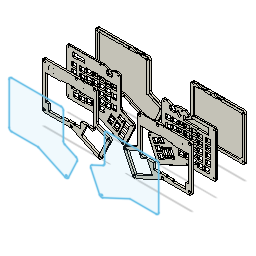
ergodox-replacement-shell-wo-wrist (Autodesk Fusion 360 design; units mm, degrees)
Autodesk Fusion 360 part; units mm, degrees
(part 1 of 3)
sketch "ErgoDOX Case Layer 5 Bottom - Left" plane through (0, 0, 0) normal (0, 0, 1) x (1, 0, 0)
  line L0 (196, 16) -> (196, 16)
  arc A0 (20, -23.440584) -> (27, -30.440584) centre (27, -23.440584) ccw
  line L1 (181.0868, 176.698) -> (181.0868, 97.809302)
  arc A1 (181.0868, 97.809302) -> (185.12868, 91.465051) centre (188.0868, 97.809302) ccw
  arc A2 (221.924958, 66.584374) -> (218.538915, 75.886932) centre (215.580794, 69.542681) ccw
  line L2 (196, 16) -> (196, 16)
  arc A3 (27, 183.698) -> (20, 176.698) centre (27, 176.698) ccw
  arc A4 (181.0868, 176.698) -> (174.0868, 183.698) centre (174.0868, 176.698) ccw
  line L3 (27, 183.698) -> (174.0868, 183.698)
  arc A5 (172.222356, -30.440584) -> (178.56652, -26.398891) centre (172.222356, -23.440584) ccw
  line L4 (185.12868, 91.465051) -> (218.538915, 75.886932)
  line L5 (20, -23.440584) -> (20, 176.698)
  line L6 (221.924958, 66.584374) -> (178.56652, -26.398891)
  line L7 (172.222356, -30.440584) -> (27, -30.440584)
ref_plane "WorkPlane1" through (0, 0, 160) normal (0, 0, 1) x (1, 0, 0)
sketch "ErgoDOX Case Layer 2 Spacer - Left" plane through (0, 0, 160) normal (0, 0, 1) x (1, 0, 0)
  arc A0 (221.924958, 66.584374) -> (218.538915, 75.886932) centre (215.580794, 69.542681) ccw
  line L0 (158.179361, 73.087383) -> (168.641234, 68.208931)
  line L1 (170.666518, 68.946074) -> (177.643945, 83.909215)
  arc A1 (212.634676, 67.592769) -> (212.143248, 68.942958) centre (211.713868, 68.02215) ccw
  circle A2 centre (174.816574, 177.434124) radius 1.5
  circle A3 centre (106.66988, 49.713) radius 1.5
  circle A4 centre (26.263876, 53.119376) radius 1.5
  arc A5 (28.89, 74.119191) -> (29.89, 73.119191) centre (29.89, 74.119191) ccw
  arc A6 (181.0868, 176.698) -> (174.0868, 183.698) centre (174.0868, 176.698) ccw
  line L2 (165.9738, 183.698) -> (174.0868, 183.698)
  arc A7 (158.608741, 75.024191) -> (158.179361, 73.087383) centre (158.608741, 74.008191) ccw
  circle A8 centre (216.558535, 69.898485) radius 1.5
  arc A9 (178.994134, 84.400644) -> (177.643945, 83.909215) centre (178.564754, 83.479835) ccw
  line L3 (152.0941, 178.58498) -> (144.7507, 178.58498)
  line L4 (165.9738, 183.698) -> (152.0941, 178.58498)
  line L5 (172.184141, 150.716191) -> (172.1968, 85.4)
  arc A10 (168.641234, 68.208931) -> (170.666518, 68.946074) centre (169.285305, 69.590144) ccw
  line L6 (142.037, 163.5842) -> (142.037, 177.0842)
  line L7 (178.994134, 84.400644) -> (212.143248, 68.942958)
  arc A11 (181.0868, 97.809302) -> (185.12868, 91.465051) centre (188.0868, 97.809302) ccw
  circle A12 centre (26.263876, 177.434124) radius 1.5
  line L8 (28.89, 74.119191) -> (28.89, 148.827191)
  arc A13 (29.89, 149.827191) -> (28.89, 148.827191) centre (29.89, 148.827191) ccw
  line L9 (212.634676, 67.592769) -> (189.126113, 17.178493)
  line L10 (27, 183.698) -> (130.871, 183.698)
  line L11 (181.0868, 176.698) -> (181.0868, 97.809302)
  circle A14 centre (121.3333, 179.253) radius 1.5
  line L12 (134.084141, 73.500191) -> (134.084141, 58.260191)
  line L13 (95.153498, 57.244191) -> (78.458141, 57.244191)
  line L14 (185.12868, 91.465051) -> (218.538915, 75.886932)
  arc A15 (74.902141, 149.827191) -> (76.426141, 151.351191) centre (74.902141, 151.351191) ccw
  arc A16 (38.326141, 71.595191) -> (36.802141, 73.119191) centre (36.802141, 71.595191) ccw
  arc A17 (75.918141, 54.069191) -> (76.934141, 55.085191) centre (75.918141, 55.085191) ccw
  arc A18 (77.442141, 153.002191) -> (76.426141, 151.986191) centre (77.442141, 151.986191) ccw
  arc A19 (134.288319, 152.494191) -> (135.608141, 151.732191) centre (135.608141, 153.256191) ccw
  arc A20 (151.470453, 72.856121) -> (150.08924, 75.024191) centre (150.08924, 73.500191) ccw
  line L15 (113.002141, 58.831691) -> (97.508141, 58.831691)
  line L16 (145.3078, 178.58498) -> (144.7507, 178.58498)
  line L17 (142.037, 177.0842) -> (154.8078, 177.0842)
  line L18 (20, -23.440584) -> (20, 176.698)
  arc A21 (133.068141, 57.244191) -> (134.084141, 58.260191) centre (133.068141, 58.260191) ccw
  arc A22 (115.145355, 153.954691) -> (116.558141, 153.002191) centre (116.558141, 154.526191) ccw
  arc A23 (187.775924, 16.687064) -> (189.126113, 17.178493) centre (188.205304, 17.607873) ccw
  line L19 (154.8078, 163.5842) -> (142.037, 163.5842)
  arc A24 (114.414927, 57.879191) -> (113.002141, 58.831691) centre (113.002141, 57.307691) ccw
  line L20 (152.0941, 178.58498) -> (151.3078, 178.58498)
  arc A25 (93.952141, 153.002191) -> (95.364927, 153.954691) centre (93.952141, 154.526191) ccw
  line L21 (171.168141, 75.024191) -> (158.608741, 75.024191)
  line L22 (75.918141, 54.069191) -> (39.342141, 54.069191)
  line L23 (135.608141, 151.732191) -> (171.168141, 151.732191)
  arc A26 (96.306784, 154.589691) -> (95.364927, 153.954691) centre (96.306784, 153.573691) ccw
  line L24 (172.222356, -30.440584) -> (27, -30.440584)
  line L25 (96.306784, 154.589691) -> (114.203498, 154.589691)
  arc A27 (20, -23.440584) -> (27, -30.440584) centre (27, -23.440584) ccw
  arc A28 (172.222356, -30.440584) -> (178.56652, -26.398891) centre (172.222356, -23.440584) ccw
  arc A29 (136.870218, 41.545816) -> (137.361647, 40.195627) centre (137.791027, 41.116436) ccw
  arc A30 (97.508141, 58.831691) -> (96.095355, 57.879191) centre (97.508141, 57.307691) ccw
  line L26 (172.184141, 150.716191) -> (172.184141, 76.040191)
  circle A31 centre (26.263876, -24.176684) radius 1.5
  line L27 (154.8078, 177.0842) -> (154.8078, 163.5842)
  arc A32 (171.168141, 75.024191) -> (172.184141, 76.040191) centre (171.168141, 76.040191) ccw
  arc A33 (78.458141, 57.244191) -> (76.934141, 55.720191) centre (78.458141, 55.720191) ccw
  line L28 (76.934141, 55.720191) -> (76.934141, 55.085191)
  line L29 (116.558141, 153.002191) -> (133.408437, 153.002191)
  line L30 (133.068141, 57.244191) -> (115.356784, 57.244191)
  arc A34 (134.288319, 152.494191) -> (133.408437, 153.002191) centre (133.408437, 151.986191) ccw
  arc A35 (115.145355, 153.954691) -> (114.203498, 154.589691) centre (114.203498, 153.573691) ccw
  arc A36 (135.608141, 75.024191) -> (134.084141, 73.500191) centre (135.608141, 73.500191) ccw
  line L31 (38.307845, 160.233267) -> (40.807845, 160.233267)
  line L32 (52.807845, 158.233267) -> (52.807845, 160.233267)
  arc A37 (38.326141, 55.085191) -> (39.342141, 54.069191) centre (39.342141, 55.085191) ccw
  line L33 (136.870218, 41.545816) -> (151.470453, 72.856121)
  line L34 (40.807845, 158.233267) -> (52.807845, 158.233267)
  line L35 (40.807845, 158.233267) -> (40.807845, 160.233267)
  line L36 (77.442141, 153.002191) -> (93.952141, 153.002191)
  line L37 (150.08924, 75.024191) -> (135.608141, 75.024191)
  circle A38 centre (172.941013, -24.568646) radius 1.5
  line L38 (76.426141, 151.351191) -> (76.426141, 151.986191)
  line L39 (36.802141, 73.119191) -> (29.89, 73.119191)
  arc A39 (27, 183.698) -> (20, 176.698) centre (27, 176.698) ccw
  line L40 (144.7507, 178.58498) -> (130.871, 183.698)
  line L41 (38.326141, 55.085191) -> (38.326141, 71.595191)
  line L42 (221.924958, 66.584374) -> (178.56652, -26.398891)
  line L43 (52.807845, 170.435327) -> (52.807845, 172.435327)
  line L44 (40.807845, 170.435327) -> (40.807845, 172.435327)
  arc A40 (114.414927, 57.879191) -> (115.356784, 57.244191) centre (115.356784, 58.260191) ccw
  line L45 (187.775924, 16.687064) -> (137.361647, 40.195627)
  line L46 (38.307845, 170.435327) -> (40.807845, 170.435327)
  line L47 (29.89, 149.827191) -> (74.902141, 149.827191)
  line L48 (40.807845, 172.435327) -> (52.807845, 172.435327)
  arc A41 (172.184141, 150.716191) -> (171.168141, 151.732191) centre (171.168141, 150.716191) ccw
  arc A42 (95.153498, 57.244191) -> (96.095355, 57.879191) centre (95.153498, 58.260191) ccw
  line L49 (52.807845, 170.435327) -> (75, 170.435327)
  line L50 (75, 170.435327) -> (75, 160.233267)
  line L51 (52.807845, 160.233267) -> (75, 160.233267)
  line L52 (38.307845, 160.233267) -> (38.307845, 170.435327)
sketch "ErgoDOX Case Layer 1 Top - Left" plane through (0, 0, 160) normal (0, 0, 1) x (1, 0, 0)
  line L0 (172.222356, -30.440584) -> (27, -30.440584)
  line L1 (20, -23.440584) -> (20, 176.698)
  line L2 (172.184141, 150.716191) -> (172.184141, 76.040191)
  arc A0 (172.184141, 150.716191) -> (171.168141, 151.732191) centre (171.168141, 150.716191) ccw
  arc A1 (172.222356, -30.440584) -> (178.56652, -26.398891) centre (172.222356, -23.440584) ccw
  circle A2 centre (26.263876, -24.176684) radius 1.5
  line L3 (135.608141, 151.732191) -> (171.168141, 151.732191)
  circle A3 centre (172.941013, -24.568646) radius 1.5
  line L4 (221.924958, 66.584374) -> (178.56652, -26.398891)
  line L5 (171.168141, 75.024191) -> (158.608741, 75.024191)
  arc A4 (20, -23.440584) -> (27, -30.440584) centre (27, -23.440584) ccw
  arc A5 (136.870218, 41.545816) -> (137.361647, 40.195627) centre (137.791027, 41.116436) ccw
  line L6 (96.306784, 154.589691) -> (114.203498, 154.589691)
  arc A6 (134.288319, 152.494191) -> (133.408437, 153.002191) centre (133.408437, 151.986191) ccw
  line L7 (178.994134, 84.400644) -> (212.143248, 68.942958)
  line L8 (181.0868, 176.698) -> (181.0868, 97.809302)
  line L9 (133.068141, 57.244191) -> (115.356784, 57.244191)
  arc A7 (114.414927, 57.879191) -> (113.002141, 58.831691) centre (113.002141, 57.307691) ccw
  line L10 (27, 183.698) -> (174.0868, 183.698)
  line L11 (113.002141, 58.831691) -> (97.508141, 58.831691)
  circle A8 centre (216.558535, 69.898485) radius 1.5
  circle A9 centre (106.66988, 49.713) radius 1.5
  line L12 (212.634676, 67.592769) -> (189.126113, 17.178493)
  line L13 (116.558141, 153.002191) -> (133.408437, 153.002191)
  circle A10 centre (121.3333, 179.253) radius 1.5
  line L14 (185.12868, 91.465051) -> (218.538915, 75.886932)
  line L15 (77.442141, 153.002191) -> (93.952141, 153.002191)
  arc A11 (158.608741, 75.024191) -> (158.179361, 73.087383) centre (158.608741, 74.008191) ccw
  arc A12 (178.994134, 84.400644) -> (177.643945, 83.909215) centre (178.564754, 83.479835) ccw
  arc A13 (78.458141, 57.244191) -> (76.934141, 55.720191) centre (78.458141, 55.720191) ccw
  line L16 (136.870218, 41.545816) -> (151.470453, 72.856121)
  arc A14 (115.145355, 153.954691) -> (116.558141, 153.002191) centre (116.558141, 154.526191) ccw
  arc A15 (93.952141, 153.002191) -> (95.364927, 153.954691) centre (93.952141, 154.526191) ccw
  line L17 (172.184141, 150.716191) -> (172.1968, 85.4)
  arc A16 (77.442141, 153.002191) -> (76.426141, 151.986191) centre (77.442141, 151.986191) ccw
  arc A17 (212.634676, 67.592769) -> (212.143248, 68.942958) centre (211.713868, 68.02215) ccw
  arc A18 (27, 183.698) -> (20, 176.698) centre (27, 176.698) ccw
  line L18 (150.08924, 75.024191) -> (135.608141, 75.024191)
  line L19 (76.426141, 151.351191) -> (76.426141, 151.986191)
  circle A19 centre (174.816574, 177.434124) radius 1.5
  arc A20 (151.470453, 72.856121) -> (150.08924, 75.024191) centre (150.08924, 73.500191) ccw
  arc A21 (96.306784, 154.589691) -> (95.364927, 153.954691) centre (96.306784, 153.573691) ccw
  arc A22 (115.145355, 153.954691) -> (114.203498, 154.589691) centre (114.203498, 153.573691) ccw
  arc A23 (133.068141, 57.244191) -> (134.084141, 58.260191) centre (133.068141, 58.260191) ccw
  arc A24 (28.89, 74.119191) -> (29.89, 73.119191) centre (29.89, 74.119191) ccw
  arc A25 (38.326141, 71.595191) -> (36.802141, 73.119191) centre (36.802141, 71.595191) ccw
  line L20 (134.084141, 73.500191) -> (134.084141, 58.260191)
  line L21 (76.934141, 55.720191) -> (76.934141, 55.085191)
  arc A26 (221.924958, 66.584374) -> (218.538915, 75.886932) centre (215.580794, 69.542681) ccw
  line L22 (95.153498, 57.244191) -> (78.458141, 57.244191)
  arc A27 (29.89, 149.827191) -> (28.89, 148.827191) centre (29.89, 148.827191) ccw
  line L23 (187.775924, 16.687064) -> (137.361647, 40.195627)
  arc A28 (135.608141, 75.024191) -> (134.084141, 73.500191) centre (135.608141, 73.500191) ccw
  line L24 (75.918141, 54.069191) -> (39.342141, 54.069191)
  circle A29 centre (26.263876, 177.434124) radius 1.5
  arc A30 (38.326141, 55.085191) -> (39.342141, 54.069191) centre (39.342141, 55.085191) ccw
  line L25 (38.326141, 55.085191) -> (38.326141, 71.595191)
  line L26 (36.802141, 73.119191) -> (29.89, 73.119191)
  arc A31 (168.641234, 68.208931) -> (170.666518, 68.946074) centre (169.285305, 69.590144) ccw
  circle A32 centre (26.263876, 53.119376) radius 1.5
  arc A33 (181.0868, 176.698) -> (174.0868, 183.698) centre (174.0868, 176.698) ccw
  arc A34 (97.508141, 58.831691) -> (96.095355, 57.879191) centre (97.508141, 57.307691) ccw
  arc A35 (95.153498, 57.244191) -> (96.095355, 57.879191) centre (95.153498, 58.260191) ccw
  arc A36 (75.918141, 54.069191) -> (76.934141, 55.085191) centre (75.918141, 55.085191) ccw
  line L27 (28.89, 74.119191) -> (28.89, 148.827191)
  line L28 (158.179361, 73.087383) -> (168.641234, 68.208931)
  line L29 (170.666518, 68.946074) -> (177.643945, 83.909215)
  line L30 (29.89, 149.827191) -> (74.902141, 149.827191)
  arc A37 (74.902141, 149.827191) -> (76.426141, 151.351191) centre (74.902141, 151.351191) ccw
  arc A38 (134.288319, 152.494191) -> (135.608141, 151.732191) centre (135.608141, 153.256191) ccw
  arc A39 (171.168141, 75.024191) -> (172.184141, 76.040191) centre (171.168141, 76.040191) ccw
  arc A40 (114.414927, 57.879191) -> (115.356784, 57.244191) centre (115.356784, 58.260191) ccw
  arc A41 (187.775924, 16.687064) -> (189.126113, 17.178493) centre (188.205304, 17.607873) ccw
  arc A42 (181.0868, 97.809302) -> (185.12868, 91.465051) centre (188.0868, 97.809302) ccw
ref_plane "WorkPlane2" through (0, 0, 85) normal (0, 0, 1) x (1, 0, 0)
sketch "ErgoDOX Case Layer 3 Plate - Left" plane through (0, 0, 85) normal (0, 0, 1) x (1, 0, 0)
  line L0 (131.302846, 60.053437) -> (131.302846, 61.033877)
  line L1 (98.282846, 71.140537) -> (98.282846, 66.131657)
  line L2 (74.152846, 69.867997) -> (74.152846, 70.848437)
  line L3 (74.965646, 57.858877) -> (74.965646, 61.358997)
  line L4 (116.520046, 64.533997) -> (116.520046, 61.033877)
  line L5 (131.302846, 61.033877) -> (132.115646, 61.033877)
  line L6 (74.965646, 61.358997) -> (74.152846, 61.358997)
  line L7 (97.470046, 74.640657) -> (97.470046, 71.140537)
  line L8 (113.065646, 74.640657) -> (112.252846, 74.640657)
  line L9 (98.282846, 66.131657) -> (97.470046, 66.131657)
  line L10 (94.015646, 111.142997) -> (93.202846, 111.142997)
  line L11 (132.115646, 102.633997) -> (131.302846, 102.633997)
  line L12 (112.252846, 113.721097) -> (98.282846, 113.721097)
  line L13 (131.302846, 99.133877) -> (132.115646, 99.133877)
  line L14 (131.302846, 102.633997) -> (131.302846, 107.642877)
  line L15 (116.520046, 107.642877) -> (117.332846, 107.642877)
  line L16 (94.015646, 107.642877) -> (94.015646, 111.142997)
  line L17 (97.470046, 100.731537) -> (98.282846, 100.731537)
  line L18 (98.282846, 99.751097) -> (112.252846, 99.751097)
  line L19 (113.065646, 100.731537) -> (113.065646, 104.231657)
  line L20 (98.282846, 104.231657) -> (97.470046, 104.231657)
  line L21 (93.202846, 99.133877) -> (94.015646, 99.133877)
  line L22 (74.965646, 123.517877) -> (74.965646, 127.017997)
  line L23 (117.332846, 131.173437) -> (117.332846, 130.192997)
  line L24 (131.302846, 130.192997) -> (131.302846, 131.173437)
  line L25 (60.182846, 108.948437) -> (60.182846, 107.967997)
  line L26 (98.282846, 131.790657) -> (97.470046, 131.790657)
  line L27 (113.065646, 128.290537) -> (113.065646, 131.790657)
  line L28 (97.470046, 112.740657) -> (97.470046, 109.240537)
  line L29 (93.202846, 112.123437) -> (79.232846, 112.123437)
  line L30 (78.420046, 107.642877) -> (79.232846, 107.642877)
  line L31 (113.065646, 109.240537) -> (113.065646, 112.740657)
  line L32 (78.420046, 99.133877) -> (79.232846, 99.133877)
  line L33 (93.202846, 102.633997) -> (93.202846, 107.642877)
  line L34 (74.152846, 95.958877) -> (74.965646, 95.958877)
  line L35 (98.282846, 112.740657) -> (97.470046, 112.740657)
  line L36 (98.282846, 100.731537) -> (98.282846, 99.751097)
  line L37 (94.015646, 102.633997) -> (93.202846, 102.633997)
  line L38 (131.302846, 112.123437) -> (117.332846, 112.123437)
  line L39 (116.520046, 111.142997) -> (116.520046, 107.642877)
  line L40 (79.232846, 107.642877) -> (79.232846, 102.633997)
  line L41 (97.470046, 104.231657) -> (97.470046, 100.731537)
  line L42 (112.252846, 112.740657) -> (112.252846, 113.721097)
  line L43 (117.332846, 98.153437) -> (131.302846, 98.153437)
  line L44 (112.252846, 128.290537) -> (113.065646, 128.290537)
  line L45 (131.302846, 140.733997) -> (131.302846, 145.742877)
  line L46 (131.302846, 118.183877) -> (132.115646, 118.183877)
  line L47 (97.470046, 142.331657) -> (97.470046, 138.831537)
  line L48 (131.302846, 136.253437) -> (131.302846, 137.233877)
  line L49 (112.252846, 150.840657) -> (112.252846, 151.821097)
  line L50 (98.282846, 147.340537) -> (98.282846, 142.331657)
  line L51 (113.065646, 138.831537) -> (113.065646, 142.331657)
  line L52 (117.332846, 140.733997) -> (116.520046, 140.733997)
  line L53 (132.115646, 149.242997) -> (131.302846, 149.242997)
  line L54 (132.115646, 130.192997) -> (131.302846, 130.192997)
  line L55 (132.115646, 137.233877) -> (132.115646, 140.733997)
  line L56 (74.152846, 118.508997) -> (74.152846, 123.517877)
  line L57 (113.065646, 123.281657) -> (112.252846, 123.281657)
  line L58 (112.252846, 132.771097) -> (98.282846, 132.771097)
  line L59 (74.965646, 127.017997) -> (74.152846, 127.017997)
  line L60 (98.282846, 132.771097) -> (98.282846, 131.790657)
  line L61 (117.332846, 118.183877) -> (117.332846, 117.203437)
  line L62 (132.115646, 121.683997) -> (131.302846, 121.683997)
  line L63 (131.302846, 126.692877) -> (132.115646, 126.692877)
  line L64 (74.152846, 108.948437) -> (60.182846, 108.948437)
  line L65 (59.370046, 104.467877) -> (60.182846, 104.467877)
  line L66 (60.182846, 115.008877) -> (60.182846, 114.028437)
  line L67 (98.282846, 128.290537) -> (98.282846, 123.281657)
  line L68 (74.152846, 127.017997) -> (74.152846, 127.998437)
  line L69 (74.152846, 123.517877) -> (74.965646, 123.517877)
  line L70 (59.370046, 115.008877) -> (60.182846, 115.008877)
  line L71 (98.282846, 119.781537) -> (98.282846, 118.801097)
  line L72 (59.370046, 107.967997) -> (59.370046, 104.467877)
  line L73 (59.370046, 95.958877) -> (60.182846, 95.958877)
  line L74 (98.282846, 118.801097) -> (112.252846, 118.801097)
  line L75 (98.282846, 137.851097) -> (112.252846, 137.851097)
  line L76 (59.370046, 127.017997) -> (59.370046, 123.517877)
  line L77 (98.282846, 142.331657) -> (97.470046, 142.331657)
  line L78 (117.332846, 149.242997) -> (116.520046, 149.242997)
  line L79 (60.182846, 123.517877) -> (60.182846, 118.508997)
  line L80 (94.015646, 64.533997) -> (93.202846, 64.533997)
  line L81 (117.332846, 145.742877) -> (117.332846, 140.733997)
  line L82 (112.252846, 147.340537) -> (113.065646, 147.340537)
  line L83 (78.420046, 64.533997) -> (78.420046, 61.033877)
  line L84 (78.420046, 69.542877) -> (79.232846, 69.542877)
  line L85 (93.202846, 69.542877) -> (94.015646, 69.542877)
  line L86 (112.252846, 142.331657) -> (112.252846, 147.340537)
  line L87 (60.182846, 127.998437) -> (60.182846, 127.017997)
  line L88 (59.370046, 123.517877) -> (60.182846, 123.517877)
  line L89 (79.232846, 73.042997) -> (78.420046, 73.042997)
  line L90 (93.202846, 73.042997) -> (93.202846, 74.023437)
  line L91 (116.520046, 137.233877) -> (117.332846, 137.233877)
  line L92 (60.182846, 118.508997) -> (59.370046, 118.508997)
  line L93 (59.370046, 118.508997) -> (59.370046, 115.008877)
  line L94 (79.232846, 64.533997) -> (78.420046, 64.533997)
  line L95 (97.470046, 147.340537) -> (98.282846, 147.340537)
  line L96 (112.252846, 80.701097) -> (112.252846, 81.681537)
  line L97 (132.115646, 92.092997) -> (131.302846, 92.092997)
  line L98 (98.282846, 94.671097) -> (98.282846, 93.690657)
  line L99 (98.282846, 81.681537) -> (98.282846, 80.701097)
  line L100 (116.520046, 92.092997) -> (116.520046, 88.592877)
  line L101 (131.302846, 80.083877) -> (132.115646, 80.083877)
  line L102 (135.570046, 78.813877) -> (136.382846, 78.813877)
  line L103 (136.382846, 78.813877) -> (136.382846, 77.833437)
  line L104 (59.370046, 69.867997) -> (59.370046, 66.367877)
  line L105 (98.282846, 93.690657) -> (97.470046, 93.690657)
  line L106 (98.282846, 85.181657) -> (97.470046, 85.181657)
  line L107 (131.302846, 88.592877) -> (132.115646, 88.592877)
  line L108 (117.332846, 73.042997) -> (116.520046, 73.042997)
  line L109 (112.252846, 74.640657) -> (112.252846, 75.621097)
  line L110 (97.470046, 85.181657) -> (97.470046, 81.681537)
  line L111 (117.332846, 79.103437) -> (131.302846, 79.103437)
  line L112 (117.332846, 69.542877) -> (117.332846, 64.533997)
  line L113 (59.370046, 57.858877) -> (60.182846, 57.858877)
  line L114 (112.252846, 93.690657) -> (112.252846, 94.671097)
  line L115 (112.252846, 81.681537) -> (113.065646, 81.681537)
  line L116 (117.332846, 80.083877) -> (117.332846, 79.103437)
  line L117 (136.382846, 87.322877) -> (136.382846, 82.313997)
  line L118 (132.115646, 80.083877) -> (132.115646, 83.583997)
  line L119 (113.065646, 85.181657) -> (112.252846, 85.181657)
  line L120 (98.282846, 80.701097) -> (112.252846, 80.701097)
  line L121 (112.252846, 85.181657) -> (112.252846, 90.190537)
  line L122 (117.332846, 92.092997) -> (116.520046, 92.092997)
  line L123 (135.570046, 87.322877) -> (136.382846, 87.322877)
  line L124 (135.570046, 82.313997) -> (135.570046, 78.813877)
  line L125 (150.352846, 78.813877) -> (151.165646, 78.813877)
  line L126 (151.165646, 78.813877) -> (151.165646, 82.313997)
  line L127 (132.115646, 83.583997) -> (131.302846, 83.583997)
  line L128 (151.165646, 90.822997) -> (150.352846, 90.822997)
  line L129 (74.152846, 70.848437) -> (60.182846, 70.848437)
  line L130 (113.065646, 81.681537) -> (113.065646, 85.181657)
  line L131 (150.352846, 87.322877) -> (151.165646, 87.322877)
  line L132 (98.282846, 90.190537) -> (98.282846, 85.181657)
  line L133 (113.065646, 93.690657) -> (112.252846, 93.690657)
  line L134 (112.252846, 90.190537) -> (113.065646, 90.190537)
  line L135 (164.922286, 125.953737) -> (164.922286, 125.140937)
  line L136 (164.922286, 125.140937) -> (159.913406, 125.140937)
  line L137 (156.413286, 125.953737) -> (156.413286, 125.140937)
  line L138 (170.215646, 139.461457) -> (169.402846, 139.461457)
  line L139 (169.402846, 134.980897) -> (169.402846, 135.961337)
  line L140 (156.413286, 125.140937) -> (155.432846, 125.140937)
  line L141 (155.432846, 111.170937) -> (156.413286, 111.170937)
  line L142 (159.913406, 125.953737) -> (156.413286, 125.953737)
  line L143 (155.432846, 147.970457) -> (154.620046, 147.970457)
  line L144 (169.402846, 135.961337) -> (170.215646, 135.961337)
  line L145 (168.422406, 125.140937) -> (168.422406, 125.953737)
  line L146 (169.402846, 144.470337) -> (170.215646, 144.470337)
  line L147 (155.432846, 125.140937) -> (155.432846, 111.170937)
  line L148 (155.432846, 144.470337) -> (155.432846, 139.461457)
  line L149 (169.402846, 139.461457) -> (169.402846, 144.470337)
  line L150 (154.620046, 144.470337) -> (155.432846, 144.470337)
  line L151 (159.913406, 125.140937) -> (159.913406, 125.953737)
  line L152 (169.402846, 148.950897) -> (155.432846, 148.950897)
  line L153 (168.422406, 125.953737) -> (164.922286, 125.953737)
  line L154 (154.620046, 147.970457) -> (154.620046, 144.470337)
  line L155 (155.432846, 148.950897) -> (155.432846, 147.970457)
  line L156 (154.620046, 135.961337) -> (155.432846, 135.961337)
  line L157 (155.432846, 135.961337) -> (155.432846, 134.980897)
  line L158 (155.432846, 134.980897) -> (169.402846, 134.980897)
  line L159 (170.215646, 135.961337) -> (170.215646, 139.461457)
  line L160 (154.620046, 139.461457) -> (154.620046, 135.961337)
  line L161 (168.422406, 111.170937) -> (169.402846, 111.170937)
  line L162 (155.432846, 139.461457) -> (154.620046, 139.461457)
  line L163 (168.422406, 82.595937) -> (169.402846, 82.595937)
  line L164 (159.913406, 97.378737) -> (156.413286, 97.378737)
  line L165 (159.913406, 82.595937) -> (164.922286, 82.595937)
  line L166 (155.432846, 96.565937) -> (155.432846, 82.595937)
  line L167 (40.320046, 61.358997) -> (40.320046, 57.858877)
  line L168 (55.915646, 69.867997) -> (55.102846, 69.867997)
  line L169 (55.102846, 69.867997) -> (55.102846, 70.848437)
  line L170 (164.922286, 110.358137) -> (168.422406, 110.358137)
  line L171 (136.382846, 128.922997) -> (135.570046, 128.922997)
  line L172 (135.570046, 125.422877) -> (136.382846, 125.422877)
  line L173 (55.102846, 61.358997) -> (55.102846, 66.367877)
  line L174 (55.915646, 66.367877) -> (55.915646, 69.867997)
  line L175 (55.915646, 57.858877) -> (55.915646, 61.358997)
  line L176 (156.413286, 81.783137) -> (159.913406, 81.783137)
  line L177 (55.915646, 61.358997) -> (55.102846, 61.358997)
  line L178 (55.102846, 56.878437) -> (55.102846, 57.858877)
  line L179 (159.913406, 111.170937) -> (164.922286, 111.170937)
  line L180 (155.432846, 82.595937) -> (156.413286, 82.595937)
  line L181 (159.913406, 110.358137) -> (159.913406, 111.170937)
  line L182 (151.165646, 116.913877) -> (151.165646, 120.413997)
  line L183 (156.413286, 111.170937) -> (156.413286, 110.358137)
  line L184 (150.352846, 116.913877) -> (151.165646, 116.913877)
  line L185 (136.382846, 125.422877) -> (136.382846, 120.413997)
  line L186 (169.402846, 82.595937) -> (169.402846, 96.565937)
  line L187 (136.382846, 115.933437) -> (150.352846, 115.933437)
  line L188 (151.165646, 120.413997) -> (150.352846, 120.413997)
  line L189 (41.132846, 61.358997) -> (40.320046, 61.358997)
  line L190 (136.382846, 116.913877) -> (136.382846, 115.933437)
  line L191 (150.352846, 115.933437) -> (150.352846, 116.913877)
  line L192 (156.413286, 82.595937) -> (156.413286, 81.783137)
  line L193 (150.352846, 120.413997) -> (150.352846, 125.422877)
  line L194 (156.413286, 110.358137) -> (159.913406, 110.358137)
  line L195 (41.132846, 69.867997) -> (40.320046, 69.867997)
  line L196 (41.132846, 57.858877) -> (41.132846, 56.878437)
  line L197 (55.102846, 57.858877) -> (55.915646, 57.858877)
  line L198 (41.132846, 70.848437) -> (41.132846, 69.867997)
  line L199 (164.922286, 111.170937) -> (164.922286, 110.358137)
  line L200 (150.352846, 129.903437) -> (136.382846, 129.903437)
  line L201 (41.132846, 56.878437) -> (55.102846, 56.878437)
  line L202 (40.320046, 69.867997) -> (40.320046, 66.367877)
  line L203 (168.422406, 81.783137) -> (168.422406, 82.595937)
  line L204 (164.922286, 97.378737) -> (164.922286, 96.565937)
  line L205 (168.422406, 97.378737) -> (164.922286, 97.378737)
  line L206 (159.913406, 96.565937) -> (159.913406, 97.378737)
  line L207 (40.320046, 66.367877) -> (41.132846, 66.367877)
  line L208 (164.922286, 82.595937) -> (164.922286, 81.783137)
  line L209 (156.413286, 97.378737) -> (156.413286, 96.565937)
  line L210 (136.382846, 129.903437) -> (136.382846, 128.922997)
  line L211 (135.570046, 128.922997) -> (135.570046, 125.422877)
  line L212 (164.922286, 96.565937) -> (159.913406, 96.565937)
  line L213 (168.422406, 110.358137) -> (168.422406, 111.170937)
  line L214 (41.132846, 66.367877) -> (41.132846, 61.358997)
  line L215 (40.320046, 57.858877) -> (41.132846, 57.858877)
  line L216 (169.402846, 96.565937) -> (168.422406, 96.565937)
  line L217 (159.913406, 81.783137) -> (159.913406, 82.595937)
  line L218 (168.422406, 96.565937) -> (168.422406, 97.378737)
  line L219 (55.102846, 70.848437) -> (41.132846, 70.848437)
  line L220 (55.102846, 66.367877) -> (55.915646, 66.367877)
  line L221 (136.382846, 120.413997) -> (135.570046, 120.413997)
  line L222 (135.570046, 120.413997) -> (135.570046, 116.913877)
  line L223 (135.570046, 116.913877) -> (136.382846, 116.913877)
  line L224 (156.413286, 96.565937) -> (155.432846, 96.565937)
  line L225 (194.099266, 69.362537) -> (194.835866, 69.019637)
  line L226 (164.922286, 81.783137) -> (168.422406, 81.783137)
  line L227 (186.050006, 52.098157) -> (186.786606, 51.755257)
  line L228 (195.851866, 38.138317) -> (196.588466, 37.795417)
  line L229 (201.343346, 49.911217) -> (188.681446, 55.816717)
  line L230 (176.618986, 29.949357) -> (175.882386, 30.292257)
  line L231 (190.505166, 61.651097) -> (191.241766, 61.308197)
  line L232 (191.241766, 61.308197) -> (190.825206, 60.419197)
  line L233 (196.316686, 72.192097) -> (195.580086, 72.534997)
  line L234 (195.580086, 72.534997) -> (194.099266, 69.362537)
  line L235 (194.835866, 69.019637) -> (192.720046, 64.480657)
  line L236 (190.825206, 60.419197) -> (203.487106, 54.513697)
  line L237 (203.487106, 54.513697) -> (203.901126, 55.402697)
  line L238 (191.983446, 64.823557) -> (190.505166, 61.651097)
  line L239 (208.976046, 66.286597) -> (209.392606, 67.175597)
  line L240 (199.448506, 45.849757) -> (200.185106, 45.506857)
  line L241 (151.165646, 128.922997) -> (150.352846, 128.922997)
  line L242 (203.901126, 55.402697) -> (204.637726, 55.059797)
  line L243 (206.118546, 58.232257) -> (205.381946, 58.575157)
  line L244 (151.165646, 125.422877) -> (151.165646, 128.922997)
  line L245 (150.352846, 125.422877) -> (151.165646, 125.422877)
  line L246 (201.663386, 48.679317) -> (200.926786, 49.022217)
  line L247 (192.720046, 64.480657) -> (191.983446, 64.823557)
  line L248 (208.234366, 62.771237) -> (209.712646, 65.943697)
  line L249 (204.637726, 55.059797) -> (206.118546, 58.232257)
  line L250 (174.724146, 25.887897) -> (187.386046, 19.982397)
  line L251 (209.712646, 65.943697) -> (208.976046, 66.286597)
  line L252 (200.926786, 49.022217) -> (201.343346, 49.911217)
  line L253 (191.396706, 28.582837) -> (192.133306, 28.239937)
  line L254 (183.934186, 47.559177) -> (182.455906, 44.386717)
  line L255 (207.497766, 63.114137) -> (208.234366, 62.771237)
  line L256 (195.437846, 37.249317) -> (195.851866, 38.138317)
  line L257 (178.734806, 34.488337) -> (176.618986, 29.949357)
  line L258 (190.017486, 23.700957) -> (189.280886, 24.043857)
  line L259 (198.069286, 40.967877) -> (197.332686, 41.310777)
  line L260 (205.381946, 58.575157) -> (207.497766, 63.114137)
  line L261 (193.291546, 32.644297) -> (180.629646, 38.549797)
  line L262 (182.455906, 44.386717) -> (183.192506, 44.043817)
  line L263 (187.530826, 55.270617) -> (186.050006, 52.098157)
  line L264 (184.670786, 47.216277) -> (183.934186, 47.559177)
  line L265 (187.800066, 20.871397) -> (188.536666, 20.528497)
  line L266 (183.192506, 44.043817) -> (182.775946, 43.154817)
  line L267 (180.629646, 38.549797) -> (180.215626, 37.660797)
  line L268 (192.133306, 28.239937) -> (193.611586, 31.412397)
  line L269 (180.215626, 37.660797) -> (179.479026, 38.003697)
  line L270 (200.185106, 45.506857) -> (201.663386, 48.679317)
  line L271 (188.681446, 55.816717) -> (188.267426, 54.927717)
  line L272 (197.332686, 41.310777) -> (199.448506, 45.849757)
  line L273 (189.280886, 24.043857) -> (191.396706, 28.582837)
  line L274 (182.775946, 43.154817) -> (195.437846, 37.249317)
  line L275 (196.588466, 37.795417) -> (198.069286, 40.967877)
  line L276 (179.479026, 38.003697) -> (177.998206, 34.831237)
  line L277 (193.611586, 31.412397) -> (192.874986, 31.755297)
  line L278 (150.352846, 128.922997) -> (150.352846, 129.903437)
  line L279 (177.998206, 34.831237) -> (178.734806, 34.488337)
  line L280 (188.536666, 20.528497) -> (190.017486, 23.700957)
  line L281 (192.874986, 31.755297) -> (193.291546, 32.644297)
  line L282 (209.392606, 67.175597) -> (196.730706, 73.081097)
  line L283 (188.267426, 54.927717) -> (187.530826, 55.270617)
  line L284 (187.386046, 19.982397) -> (187.800066, 20.871397)
  line L285 (186.786606, 51.755257) -> (184.670786, 47.216277)
  line L286 (174.404106, 27.119797) -> (175.140706, 26.776897)
  line L287 (175.882386, 30.292257) -> (174.404106, 27.119797)
  line L288 (93.202846, 137.233877) -> (94.015646, 137.233877)
  line L289 (196.730706, 73.081097) -> (196.316686, 72.192097)
  line L290 (60.182846, 133.075897) -> (74.152846, 133.075897)
  line L291 (179.052306, 80.241357) -> (178.315706, 80.584257)
  line L292 (112.252846, 151.821097) -> (98.282846, 151.821097)
  line L293 (176.834886, 77.411797) -> (177.571486, 77.068897)
  line L294 (60.182846, 146.065457) -> (59.370046, 146.065457)
  line L295 (94.015646, 145.742877) -> (94.015646, 149.242997)
  line L296 (192.128226, 75.224857) -> (179.466326, 81.130357)
  line L297 (93.202846, 145.742877) -> (94.015646, 145.742877)
  line L298 (74.152846, 134.056337) -> (74.965646, 134.056337)
  line L299 (186.636746, 63.451957) -> (187.373346, 63.109057)
  line L300 (187.373346, 63.109057) -> (188.854166, 66.281517)
  line L301 (173.240786, 69.700357) -> (173.977386, 69.357457)
  line L302 (93.202846, 150.223437) -> (79.232846, 150.223437)
  line L303 (98.282846, 150.840657) -> (97.470046, 150.840657)
  line L304 (74.965646, 137.556457) -> (74.152846, 137.556457)
  line L305 (79.232846, 149.242997) -> (78.420046, 149.242997)
  line L306 (60.182846, 147.045897) -> (60.182846, 146.065457)
  line L307 (60.182846, 137.556457) -> (59.370046, 137.556457)
  line L308 (74.152846, 133.075897) -> (74.152846, 134.056337)
  line L309 (175.140706, 26.776897) -> (174.724146, 25.887897)
  line L310 (97.470046, 150.840657) -> (97.470046, 147.340537)
  line L311 (178.315706, 80.584257) -> (176.834886, 77.411797)
  line L312 (192.448266, 73.992957) -> (191.711666, 74.335857)
  line L313 (79.232846, 137.233877) -> (79.232846, 136.253437)
  line L314 (93.202846, 140.733997) -> (93.202846, 145.742877)
  line L315 (179.466326, 81.130357) -> (179.052306, 80.241357)
  line L316 (78.420046, 145.742877) -> (79.232846, 145.742877)
  line L317 (78.420046, 149.242997) -> (78.420046, 145.742877)
  line L318 (175.455666, 72.529917) -> (174.719066, 72.872817)
  line L319 (78.420046, 137.233877) -> (79.232846, 137.233877)
  line L320 (174.719066, 72.872817) -> (173.240786, 69.700357)
  line L321 (188.117566, 66.624417) -> (190.233386, 71.163397)
  line L322 (173.977386, 69.357457) -> (173.560826, 68.468457)
  line L323 (190.233386, 71.163397) -> (190.969986, 70.820497)
  line L324 (94.015646, 137.233877) -> (94.015646, 140.733997)
  line L325 (74.965646, 142.565337) -> (74.965646, 146.065457)
  line L326 (188.854166, 66.281517) -> (188.117566, 66.624417)
  line L327 (74.152846, 147.045897) -> (60.182846, 147.045897)
  line L328 (60.182846, 134.056337) -> (60.182846, 133.075897)
  line L329 (79.232846, 145.742877) -> (79.232846, 140.733997)
  line L330 (59.370046, 146.065457) -> (59.370046, 142.565337)
  line L331 (79.232846, 150.223437) -> (79.232846, 149.242997)
  line L332 (59.370046, 142.565337) -> (60.182846, 142.565337)
  line L333 (191.711666, 74.335857) -> (192.128226, 75.224857)
  line L334 (93.202846, 136.253437) -> (93.202846, 137.233877)
  line L335 (79.232846, 136.253437) -> (93.202846, 136.253437)
  line L336 (173.560826, 68.468457) -> (186.222726, 62.562957)
  line L337 (74.152846, 146.065457) -> (74.152846, 147.045897)
  line L338 (60.182846, 142.565337) -> (60.182846, 137.556457)
  line L339 (74.965646, 134.056337) -> (74.965646, 137.556457)
  line L340 (74.965646, 146.065457) -> (74.152846, 146.065457)
  line L341 (94.015646, 140.733997) -> (93.202846, 140.733997)
  line L342 (74.152846, 142.565337) -> (74.965646, 142.565337)
  line L343 (98.282846, 151.821097) -> (98.282846, 150.840657)
  line L344 (177.571486, 77.068897) -> (175.455666, 72.529917)
  line L345 (190.969986, 70.820497) -> (192.448266, 73.992957)
  line L346 (131.302846, 145.742877) -> (132.115646, 145.742877)
  line L347 (74.152846, 137.556457) -> (74.152846, 142.565337)
  line L348 (117.332846, 150.223437) -> (117.332846, 149.242997)
  line L349 (131.302846, 137.233877) -> (132.115646, 137.233877)
  line L350 (94.015646, 149.242997) -> (93.202846, 149.242997)
  line L351 (93.202846, 149.242997) -> (93.202846, 150.223437)
  line L352 (98.282846, 138.831537) -> (98.282846, 137.851097)
  line L353 (59.370046, 137.556457) -> (59.370046, 134.056337)
  line L354 (59.370046, 134.056337) -> (60.182846, 134.056337)
  line L355 (113.065646, 150.840657) -> (112.252846, 150.840657)
  line L356 (78.420046, 140.733997) -> (78.420046, 137.233877)
  line L357 (79.232846, 140.733997) -> (78.420046, 140.733997)
  line L358 (186.222726, 62.562957) -> (186.636746, 63.451957)
  line L359 (79.232846, 61.033877) -> (79.232846, 60.053437)
  line L360 (78.420046, 73.042997) -> (78.420046, 69.542877)
  line L361 (117.332846, 136.253437) -> (131.302846, 136.253437)
  line L362 (97.470046, 138.831537) -> (98.282846, 138.831537)
  line L363 (79.232846, 69.542877) -> (79.232846, 64.533997)
  line L364 (112.252846, 138.831537) -> (113.065646, 138.831537)
  line L365 (113.065646, 147.340537) -> (113.065646, 150.840657)
  line L366 (132.115646, 145.742877) -> (132.115646, 149.242997)
  line L367 (93.202846, 74.023437) -> (79.232846, 74.023437)
  line L368 (94.015646, 61.033877) -> (94.015646, 64.533997)
  line L369 (79.232846, 60.053437) -> (93.202846, 60.053437)
  line L370 (94.015646, 69.542877) -> (94.015646, 73.042997)
  line L371 (113.065646, 142.331657) -> (112.252846, 142.331657)
  line L372 (132.115646, 140.733997) -> (131.302846, 140.733997)
  line L373 (93.202846, 60.053437) -> (93.202846, 61.033877)
  line L374 (116.520046, 149.242997) -> (116.520046, 145.742877)
  line L375 (94.015646, 73.042997) -> (93.202846, 73.042997)
  line L376 (93.202846, 64.533997) -> (93.202846, 69.542877)
  line L377 (116.520046, 145.742877) -> (117.332846, 145.742877)
  line L378 (131.302846, 149.242997) -> (131.302846, 150.223437)
  line L379 (131.302846, 150.223437) -> (117.332846, 150.223437)
  line L380 (117.332846, 137.233877) -> (117.332846, 136.253437)
  line L381 (116.520046, 140.733997) -> (116.520046, 137.233877)
  line L382 (78.420046, 61.033877) -> (79.232846, 61.033877)
  line L383 (93.202846, 61.033877) -> (94.015646, 61.033877)
  line L384 (112.252846, 137.851097) -> (112.252846, 138.831537)
  line L385 (74.152846, 127.998437) -> (60.182846, 127.998437)
  line L386 (60.182846, 127.017997) -> (59.370046, 127.017997)
  line L387 (79.232846, 74.023437) -> (79.232846, 73.042997)
  line L388 (170.215646, 147.970457) -> (169.402846, 147.970457)
  line L389 (170.215646, 144.470337) -> (170.215646, 147.970457)
  line L390 (169.402846, 111.170937) -> (169.402846, 125.140937)
  line L391 (169.402846, 125.140937) -> (168.422406, 125.140937)
  line L392 (169.402846, 147.970457) -> (169.402846, 148.950897)
  line L393 (113.065646, 112.740657) -> (112.252846, 112.740657)
  line L394 (116.520046, 102.633997) -> (116.520046, 99.133877)
  line L395 (132.115646, 99.133877) -> (132.115646, 102.633997)
  line L396 (74.152846, 99.458997) -> (74.152846, 104.467877)
  line L397 (74.152846, 107.967997) -> (74.152846, 108.948437)
  line L398 (79.232846, 102.633997) -> (78.420046, 102.633997)
  line L399 (79.232846, 98.153437) -> (93.202846, 98.153437)
  line L400 (93.202846, 111.142997) -> (93.202846, 112.123437)
  line L401 (117.332846, 112.123437) -> (117.332846, 111.142997)
  line L402 (78.420046, 111.142997) -> (78.420046, 107.642877)
  line L403 (78.420046, 102.633997) -> (78.420046, 99.133877)
  line L404 (112.252846, 104.231657) -> (112.252846, 109.240537)
  line L405 (98.282846, 113.721097) -> (98.282846, 112.740657)
  line L406 (112.252846, 99.751097) -> (112.252846, 100.731537)
  line L407 (74.152846, 104.467877) -> (74.965646, 104.467877)
  line L408 (93.202846, 107.642877) -> (94.015646, 107.642877)
  line L409 (79.232846, 99.133877) -> (79.232846, 98.153437)
  line L410 (74.965646, 107.967997) -> (74.152846, 107.967997)
  line L411 (79.232846, 111.142997) -> (78.420046, 111.142997)
  line L412 (97.470046, 109.240537) -> (98.282846, 109.240537)
  line L413 (117.332846, 111.142997) -> (116.520046, 111.142997)
  line L414 (74.965646, 104.467877) -> (74.965646, 107.967997)
  line L415 (74.965646, 99.458997) -> (74.152846, 99.458997)
  line L416 (93.202846, 98.153437) -> (93.202846, 99.133877)
  line L417 (74.965646, 95.958877) -> (74.965646, 99.458997)
  line L418 (113.065646, 104.231657) -> (112.252846, 104.231657)
  line L419 (116.520046, 99.133877) -> (117.332846, 99.133877)
  line L420 (117.332846, 99.133877) -> (117.332846, 98.153437)
  line L421 (117.332846, 107.642877) -> (117.332846, 102.633997)
  line L422 (112.252846, 109.240537) -> (113.065646, 109.240537)
  line L423 (117.332846, 102.633997) -> (116.520046, 102.633997)
  line L424 (98.282846, 109.240537) -> (98.282846, 104.231657)
  line L425 (79.232846, 112.123437) -> (79.232846, 111.142997)
  line L426 (94.015646, 99.133877) -> (94.015646, 102.633997)
  line L427 (131.302846, 98.153437) -> (131.302846, 99.133877)
  line L428 (78.420046, 92.092997) -> (78.420046, 88.592877)
  line L429 (93.202846, 88.592877) -> (94.015646, 88.592877)
  line L430 (79.232846, 93.073437) -> (79.232846, 92.092997)
  line L431 (93.202846, 93.073437) -> (79.232846, 93.073437)
  line L432 (93.202846, 79.103437) -> (93.202846, 80.083877)
  line L433 (132.115646, 111.142997) -> (131.302846, 111.142997)
  line L434 (60.182846, 89.898437) -> (60.182846, 88.917997)
  line L435 (74.965646, 76.908877) -> (74.965646, 80.408997)
  line L436 (78.420046, 80.083877) -> (79.232846, 80.083877)
  line L437 (136.382846, 101.363997) -> (135.570046, 101.363997)
  line L438 (59.370046, 76.908877) -> (60.182846, 76.908877)
  line L439 (150.352846, 96.883437) -> (150.352846, 97.863877)
  line L440 (136.382846, 97.863877) -> (136.382846, 96.883437)
  line L441 (74.152846, 76.908877) -> (74.965646, 76.908877)
  line L442 (150.352846, 109.872997) -> (150.352846, 110.853437)
  line L443 (150.352846, 101.363997) -> (150.352846, 106.372877)
  line L444 (135.570046, 106.372877) -> (136.382846, 106.372877)
  line L445 (74.152846, 85.417877) -> (74.965646, 85.417877)
  line L446 (74.152846, 89.898437) -> (60.182846, 89.898437)
  line L447 (132.115646, 107.642877) -> (132.115646, 111.142997)
  line L448 (136.382846, 109.872997) -> (135.570046, 109.872997)
  line L449 (79.232846, 79.103437) -> (93.202846, 79.103437)
  line L450 (151.165646, 109.872997) -> (150.352846, 109.872997)
  line L451 (79.232846, 83.583997) -> (78.420046, 83.583997)
  line L452 (131.302846, 111.142997) -> (131.302846, 112.123437)
  line L453 (150.352846, 110.853437) -> (136.382846, 110.853437)
  line L454 (151.165646, 101.363997) -> (150.352846, 101.363997)
  line L455 (135.570046, 90.822997) -> (135.570046, 87.322877)
  line L456 (97.470046, 90.190537) -> (98.282846, 90.190537)
  line L457 (151.165646, 87.322877) -> (151.165646, 90.822997)
  line L458 (112.252846, 94.671097) -> (98.282846, 94.671097)
  line L459 (131.302846, 92.092997) -> (131.302846, 93.073437)
  line L460 (97.470046, 93.690657) -> (97.470046, 90.190537)
  line L461 (117.332846, 93.073437) -> (117.332846, 92.092997)
  line L462 (136.382846, 90.822997) -> (135.570046, 90.822997)
  line L463 (116.520046, 83.583997) -> (116.520046, 80.083877)
  line L464 (74.152846, 80.408997) -> (74.152846, 85.417877)
  line L465 (74.152846, 75.928437) -> (74.152846, 76.908877)
  line L466 (150.352846, 97.863877) -> (151.165646, 97.863877)
  line L467 (79.232846, 92.092997) -> (78.420046, 92.092997)
  line L468 (94.015646, 80.083877) -> (94.015646, 83.583997)
  line L469 (151.165646, 106.372877) -> (151.165646, 109.872997)
  line L470 (93.202846, 83.583997) -> (93.202846, 88.592877)
  line L471 (94.015646, 92.092997) -> (93.202846, 92.092997)
  line L472 (112.252846, 100.731537) -> (113.065646, 100.731537)
  line L473 (60.182846, 88.917997) -> (59.370046, 88.917997)
  line L474 (78.420046, 88.592877) -> (79.232846, 88.592877)
  line L475 (78.420046, 83.583997) -> (78.420046, 80.083877)
  line L476 (74.965646, 85.417877) -> (74.965646, 88.917997)
  line L477 (74.965646, 80.408997) -> (74.152846, 80.408997)
  line L478 (93.202846, 92.092997) -> (93.202846, 93.073437)
  line L479 (79.232846, 80.083877) -> (79.232846, 79.103437)
  line L480 (60.182846, 76.908877) -> (60.182846, 75.928437)
  line L481 (74.965646, 88.917997) -> (74.152846, 88.917997)
  line L482 (94.015646, 88.592877) -> (94.015646, 92.092997)
  line L483 (74.152846, 88.917997) -> (74.152846, 89.898437)
  line L484 (93.202846, 80.083877) -> (94.015646, 80.083877)
  line L485 (136.382846, 96.883437) -> (150.352846, 96.883437)
  line L486 (59.370046, 85.417877) -> (60.182846, 85.417877)
  line L487 (79.232846, 88.592877) -> (79.232846, 83.583997)
  line L488 (151.165646, 97.863877) -> (151.165646, 101.363997)
  line L489 (136.382846, 110.853437) -> (136.382846, 109.872997)
  line L490 (131.302846, 107.642877) -> (132.115646, 107.642877)
  line L491 (150.352846, 106.372877) -> (151.165646, 106.372877)
  line L492 (60.182846, 80.408997) -> (59.370046, 80.408997)
  line L493 (135.570046, 101.363997) -> (135.570046, 97.863877)
  line L494 (59.370046, 88.917997) -> (59.370046, 85.417877)
  line L495 (136.382846, 106.372877) -> (136.382846, 101.363997)
  line L496 (59.370046, 80.408997) -> (59.370046, 76.908877)
  line L497 (60.182846, 75.928437) -> (74.152846, 75.928437)
  line L498 (94.015646, 83.583997) -> (93.202846, 83.583997)
  line L499 (60.182846, 85.417877) -> (60.182846, 80.408997)
  line L500 (135.570046, 109.872997) -> (135.570046, 106.372877)
  line L501 (135.570046, 97.863877) -> (136.382846, 97.863877)
  line L502 (151.015786, 62.867757) -> (150.126786, 63.284317)
  line L503 (136.382846, 144.470337) -> (136.382846, 139.461457)
  line L504 (78.420046, 118.183877) -> (79.232846, 118.183877)
  line L505 (148.282746, 48.727577) -> (152.821726, 46.611757)
  line L506 (152.478826, 45.875157) -> (155.651286, 44.396877)
  line L507 (172.915666, 36.345077) -> (173.258566, 37.081677)
  line L508 (168.280166, 54.815957) -> (167.391166, 55.232517)
  line L509 (79.232846, 117.203437) -> (93.202846, 117.203437)
  line L510 (155.994186, 45.133477) -> (156.883186, 44.716917)
  line L511 (175.991606, 51.221857) -> (171.452626, 53.337677)
  line L512 (171.452626, 53.337677) -> (171.795526, 54.074277)
  line L513 (161.485666, 42.570617) -> (162.374666, 42.156597)
  line L514 (93.202846, 118.183877) -> (94.015646, 118.183877)
  line L515 (94.015646, 118.183877) -> (94.015646, 121.683997)
  line L516 (93.202846, 121.683997) -> (93.202846, 126.692877)
  line L517 (135.570046, 147.970457) -> (135.570046, 144.470337)
  line L518 (50.340346, 94.978437) -> (50.340346, 95.958877)
  line L519 (151.165646, 147.970457) -> (150.352846, 147.970457)
  line L520 (150.352846, 139.461457) -> (150.352846, 144.470337)
  line L521 (35.557546, 142.565337) -> (36.370346, 142.565337)
  line L522 (36.370346, 114.028437) -> (50.340346, 114.028437)
  line L523 (36.370346, 137.556457) -> (35.557546, 137.556457)
  line L524 (51.153146, 95.958877) -> (51.153146, 99.458997)
  line L525 (36.370346, 146.065457) -> (35.557546, 146.065457)
  line L526 (36.370346, 118.508997) -> (35.557546, 118.508997)
  line L527 (50.340346, 115.008877) -> (51.153146, 115.008877)
  line L528 (150.352846, 147.970457) -> (150.352846, 148.950897)
  line L529 (50.340346, 147.045897) -> (36.370346, 147.045897)
  line L530 (51.153146, 146.065457) -> (50.340346, 146.065457)
  line L531 (36.370346, 127.998437) -> (36.370346, 127.017997)
  line L532 (180.053066, 49.327017) -> (179.164066, 49.741037)
  line L533 (135.570046, 144.470337) -> (136.382846, 144.470337)
  line L534 (35.557546, 99.458997) -> (35.557546, 95.958877)
  line L535 (136.382846, 148.950897) -> (136.382846, 147.970457)
  line L536 (36.370346, 107.967997) -> (35.557546, 107.967997)
  line L537 (50.340346, 134.056337) -> (51.153146, 134.056337)
  line L538 (36.370346, 99.458997) -> (35.557546, 99.458997)
  line L539 (36.370346, 104.467877) -> (36.370346, 99.458997)
  line L540 (36.370346, 147.045897) -> (36.370346, 146.065457)
  line L541 (150.352846, 144.470337) -> (151.165646, 144.470337)
  line L542 (50.340346, 127.017997) -> (50.340346, 127.998437)
  line L543 (36.370346, 94.978437) -> (50.340346, 94.978437)
  line L544 (151.165646, 144.470337) -> (151.165646, 147.970457)
  line L545 (35.557546, 115.008877) -> (36.370346, 115.008877)
  line L546 (50.340346, 108.948437) -> (36.370346, 108.948437)
  line L547 (36.370346, 108.948437) -> (36.370346, 107.967997)
  line L548 (36.370346, 115.008877) -> (36.370346, 114.028437)
  line L549 (51.153146, 137.556457) -> (50.340346, 137.556457)
  line L550 (50.340346, 127.998437) -> (36.370346, 127.998437)
  line L551 (50.340346, 133.075897) -> (50.340346, 134.056337)
  line L552 (51.153146, 99.458997) -> (50.340346, 99.458997)
  line L553 (50.340346, 146.065457) -> (50.340346, 147.045897)
  line L554 (35.557546, 123.517877) -> (36.370346, 123.517877)
  line L555 (50.340346, 142.565337) -> (51.153146, 142.565337)
  line L556 (35.557546, 107.967997) -> (35.557546, 104.467877)
  line L557 (150.352846, 135.961337) -> (151.165646, 135.961337)
  line L558 (176.334506, 51.958457) -> (175.991606, 51.221857)
  line L559 (79.232846, 118.183877) -> (79.232846, 117.203437)
  line L560 (36.370346, 127.017997) -> (35.557546, 127.017997)
  line L561 (50.340346, 99.458997) -> (50.340346, 104.467877)
  line L562 (36.370346, 134.056337) -> (36.370346, 133.075897)
  line L563 (51.153146, 115.008877) -> (51.153146, 118.508997)
  line L564 (51.153146, 142.565337) -> (51.153146, 146.065457)
  line L565 (35.557546, 118.508997) -> (35.557546, 115.008877)
  line L566 (155.651286, 44.396877) -> (155.994186, 45.133477)
  line L567 (135.570046, 139.461457) -> (135.570046, 135.961337)
  line L568 (51.153146, 127.017997) -> (50.340346, 127.017997)
  line L569 (35.557546, 146.065457) -> (35.557546, 142.565337)
  line L570 (35.557546, 137.556457) -> (35.557546, 134.056337)
  line L571 (51.153146, 134.056337) -> (51.153146, 137.556457)